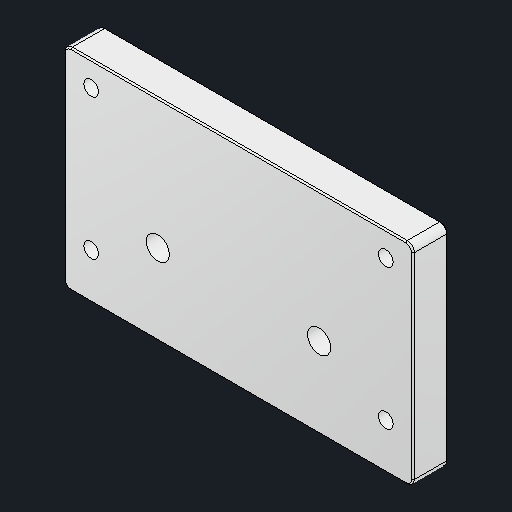
# Autodesk Inventor part: monotaro-thrust-backing-plate
Saved by Autodesk Inventor 2027.1 (Build 311270010, 270A)
## iProperties
Created: 2026-11-15
Part Number: monotaro-thrust-backing-plate
Material: Aluminum 6061
Document SubType Name: Modeling
Designer: queezz
Density: 2.7 g/cm^3
Appearance: Aluminum - Flat
Author: queezz
Autodesk Inventor part; units mm, degrees
ref_plane "YZ Plane" through (0, 0, 0) normal (1, 0, 0) x (0, 1, 0)
ref_plane "XZ Plane" through (0, 0, 0) normal (0, 1, 0) x (-1, 0, 0)
ref_plane "XY Plane" through (0, 0, 0) normal (0, 0, 1) x (1, 0, 0)
sketch "Sketch1" plane through (0, 0, 0) normal (0, 0, 1) x (1, 0, 0)
  line L0 (-49.75, -23) -> (49.75, -23)
  line L1 (49.75, -23) -> (49.75, 37)
  line L2 (49.75, 37) -> (-49.75, 37)
  line L3 (-49.75, 37) -> (-49.75, -23)
  constraints: 8 end point, 2 parallel, 1 horizontal, 1 perpendicular
extrude "10 mm backing plate blank" add sketch "Sketch1" against normal blind 10
sketch "Sketch2" plane through (0, 0, 0) normal (0, 0, 1) x (1, 0, 0)
  circle A0 centre (-23, 0) radius 2.5
  circle A1 centre (23, 0) radius 2.5
  circle A2 centre (-42, -10) radius 2.1
  circle A3 centre (-42, 30) radius 2.1
  circle A4 centre (42, -10) radius 2.1
  circle A5 centre (42, 30) radius 2.1
  constraints: 6 centre point
extrude "M6 support and M5 backing tap pilots" [suppressed]
sketch "Sketch3" plane through (0, 0, 0) normal (0, 0, 1) x (1, 0, 0)
  circle A0 centre (-23, 0) radius 3.3
  circle A1 centre (23, 0) radius 3.3
  circle A2 centre (-42, -10) radius 2.1
  circle A3 centre (-42, 30) radius 2.1
  circle A4 centre (42, -10) radius 2.1
  circle A5 centre (42, 30) radius 2.1
  constraints: 6 centre point
extrude "M6 through clearance and M5 backing tap pilots" cut sketch "Sketch3" against normal blind 10
fillet "R2 exposed plan corners" radius 2 4 edges at (49.75, -23, -5) (49.75, 37, -5) (-49.75, 37, -5) (-49.75, -23, -5)
chamfer "C0.4 outside perimeter" distance 0.4 angle 45 16 edges at (-49.1642, -22.4142, -10) (-49.1642, -22.4142, 0) (0, -23, -10) (0, -23, 0) (-49.75, 7, -10) (-49.1642, 36.4142, -10) (0, 37, -10) (49.1642, 36.4142, -10) (49.75, 7, -10) (49.1642, -22.4142, -10) (-49.1642, 36.4142, 0) (0, 37, 0) (49.1642, 36.4142, 0) (49.1642, -22.4142, 0) (49.75, 7, 0) (-49.75, 7, 0)
body "Solid1"
